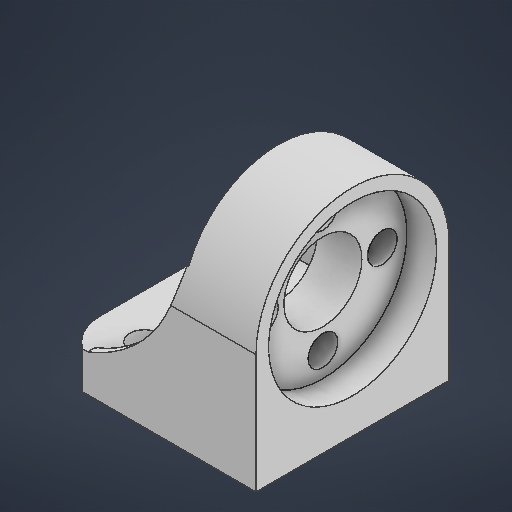
# Autodesk Inventor part: UR_rail_LeadNutHolder_v1
Saved by Autodesk Inventor 2026.2 (Build 302298010, 298A)
## iProperties
Created: 2025-11-14
Part Number: UR_rail_LeadNutHolder_v1
Material: 일반
Document SubType Name: Modeling
Designer: work
Density: 1 g/cm^3
Appearance: 기본값
Author: work
Autodesk Inventor part; units mm, degrees
ref_plane "YZ Plane" through (0, 0, 0) normal (1, 0, 0) x (0, 1, 0)
ref_plane "XZ Plane" through (0, 0, 0) normal (0, 1, 0) x (-1, 0, 0)
ref_plane "XY Plane" through (0, 0, 0) normal (0, 0, 1) x (1, 0, 0)
sketch "스케치1" plane through (0, 0, 0) normal (0, 1, 0) x (-1, 0, 0)
  line L0 (0, 8) -> (0, -8) construction
  line L1 (-6, 8) -> (-6, -8)
  line L2 (6, -8) -> (6, 8)
  arc A0 (6, 8) -> (-6, 8) centre (0, 8) ccw
  arc A1 (-6, -8) -> (6, -8) centre (0, -8) ccw
  circle A2 centre (0, 8) radius 2
  circle A3 centre (0, -8) radius 2
  line L3 (-20, 15) -> (-20, -15)
  line L4 (0, 0) -> (-20, 0) construction
  line L5 (-20, 15) -> (-10, 15)
  arc A4 (1.1881, 13.8812) -> (-10, 15) centre (-10, -41.5) ccw
  line L6 (-20, -15) -> (-10, -15)
  arc A5 (-10, -15) -> (1.1881, -13.8812) centre (-10, 41.5) ccw
  point P0 (1.1881, -13.8812)
  dimension "d0" = 16
  dimension "d1" = 6
  dimension "d2" = 4
  dimension "d3" = 4
  dimension "d4" = 20
  dimension "d5" = 30
  dimension "d6" = 10
  constraints: 16 end point, 9 point on circle, 6 centre point, 6 tangent, 3 symmetric about line, 2 coincident, 2 midpoint, 2 vertical, 1 horizontal, 1 parallel, 1 perpendicular, 1 other
  measures "d0" distance of L0.start L0.end
  measures "d1" radius of A1
  measures "d2" diameter of A2
  measures "d3" diameter of A3
  measures "d4" distance of L4.end L4.start
  measures "d5" distance of L3.start L3.end
  measures "d6" distance of L3.start L5.end
extrude "돌출1" add sketch "스케치1" along normal blind 5
sketch "스케치2" plane through (0, 5, 0) normal (0, 1, 0) x (1, 0, 0)
  line L0 (20, -15) -> (20, 15) projected
  arc A0 (10, 15) -> (-1.1881, 13.8812) centre (10, -41.5) ccw projected
  line L1 (20, -15) -> (10, -15)
  line L2 (10, -15) -> (10, 15)
  line L3 (10, 15) -> (20, 15)
  line L4 (20, 15) -> (20, -15)
  line L5 (-6, 8) -> (-6, -8) projected
  arc A1 (-6, -8) -> (-1.1881, -13.8812) centre (0, -8) ccw projected
  arc A2 (-1.1881, -13.8812) -> (10, -15) centre (10, 41.5) ccw projected
  line L6 (10, -15) -> (20, -15) projected
  line L7 (20, -15) -> (20, 15) projected
  line L8 (20, 15) -> (10, 15) projected
  arc A3 (10, 15) -> (-1.1881, 13.8812) centre (10, -41.5) ccw projected
  arc A4 (-1.1881, 13.8812) -> (-6, 8) centre (0, 8) ccw projected
  circle A5 centre (0, -8) radius 2 projected
  circle A6 centre (0, 8) radius 2 projected
  line L9 (20, 0) -> (-6, 0)
  arc A7 (-0.7921, -11.9208) -> (10, -13) centre (10, 41.5) ccw
  arc A8 (-4, -8) -> (-0.7921, -11.9208) centre (0, -8) ccw
  line L10 (-4, -8) -> (-4, 8)
  arc A9 (-0.7921, 11.9208) -> (-4, 8) centre (0, 8) ccw
  arc A10 (10, 13) -> (-0.7921, 11.9208) centre (10, -41.5) ccw
  line L11 (10, 13) -> (18, 13)
  line L12 (18, 13) -> (18, -13)
  line L13 (18, -13) -> (10, -13)
  line L14 (-7.8326, -10) -> (-13.2379, -10)
  line L15 (-7.8326, 10) -> (-13.2379, 10)
  point P0 (0, 0)
  point P1 (-2.6491, 10)
  point P2 (0.5132, 10)
  point P3 (10, -13)
  point P4 (10, 13)
  point P5 (10, -13)
  dimension "d26" = 2
  dimension "d27" = 10
  constraints: 22 end point, 10 point on circle, 4 centre point, 2 horizontal, 2 midpoint, 2 parallel, 2 symmetric about line, 1 perpendicular, 7 other
  measures "d26" radial gap between concentric circles of A2 A7
  measures "d27" distance between parallel lines of L9 L14
sketch "스케치3" plane through (20, 0, 15) normal (1, 0, 0) x (0, 0, -1)
  line L0 (15, 0) -> (15, 5) construction
  line L1 (23, 5) -> (7, 5) construction
  line L2 (15, 5) -> (15, 16) construction
  circle A0 centre (15, 16) radius 5.25
  circle A1 centre (15, 16) radius 15
  line L3 (0, 16) -> (0, 5)
  line L4 (0, 5) -> (30, 5) projected
  line L5 (30, 16) -> (30, 5)
  line L6 (30, 16) -> (0, 16) construction
  point P0 (0, 10.5)
  dimension "d9" = 11
  dimension "d10" = 10.5
  dimension "d11" = 30
  constraints: 10 end point, 2 centre point, 2 coincident, 2 midpoint, 2 point on circle, 2 vertical, 1 horizontal, 1 point on line
  measures "d9" distance of L0.end L2.end
  measures "d10" diameter of A0
  measures "d11" diameter of A1
extrude "돌출2" add sketch "스케치3" against normal blind 10 contours A1 L4 | L5 L4 A1 | A1 L4 L3 picked at (15.2109, 6.9294)
sketch "스케치4" plane through (20, 0, 15) normal (1, 0, 0) x (0, 0, -1)
  circle A0 centre (15, 16) radius 5.25 projected
  line L0 (0, 0) -> (30, 0) projected
  line L1 (30, 0) -> (30, 16) projected
  arc A1 (30, 16) -> (0, 16) centre (15, 16) ccw projected
  line L2 (0, 0) -> (0, 16) projected
  circle A2 centre (15, 16) radius 11.3
  point P0 (15, 0)
  dimension "d15" = 22.6
  constraints: 1 centre point, 1 coincident
  measures "d15" diameter of A2
extrude "돌출3" cut sketch "스케치4" against normal blind 4 contours A2
sketch "스케치5" plane through (16, 16, 0) normal (1, 0, 0) x (0, 0, -1)
  circle A0 centre (0, 0) radius 11.3 projected
  circle A1 centre (0, 0) radius 5.25 projected
  line L0 (0, 0) -> (0, 8) construction
  circle A2 centre (0, 8) radius 2
  circle A3 centre (-8, 0) radius 2
  circle A4 centre (0, -8) radius 2
  circle A5 centre (8, 0) radius 2
  point P0 (0, -16)
  dimension "d18" = 8
  dimension "d19" = 4
  dimension "d22" = 360
  constraints: 4 centre point, 2 end point, 1 coincident, 1 vertical, 9 other
  measures "d18" distance of L0.start L0.end
  measures "d19" diameter of A2
extrude "돌출4" cut sketch "스케치5" against normal through all contours A2 | A3 | A4 | A5
extrude "돌출5" add sketch "스케치2" along normal up to surface contours A2 A1 L5 L9 L10 A8 A7 L2 | A7 A8 L10 L9 L2 | L2 A10 A9 L10 L9 L5 A4 A0 | L9 L10 A9 A10 L2 | A5 | A6 round surface about axis through (20, 16, 0) along (-1, 0, 0) radius 15 far side no
sketch "스케치6" plane through (20, 0, -15) normal (0, 0, -1) x (-1, 0, 0)
  line L0 (0, 16) -> (0, 16) projected
  line L1 (0, 16) -> (10, 16) projected
  line L2 (0, 16) -> (10, 16) projected
  line L3 (10, 0) -> (21.1881, 0) projected
  line L4 (21.1881, 0) -> (21.1881, 21.6844) projected
  line L5 (10, 0) -> (10, 16) projected
  arc A0 (10, 23.4833) -> (22.6491, 5) centre (29.8288, 23.4833) ccw
  line L6 (10, 23.4833) -> (10, 31) projected
  line L7 (26, 28.6886) -> (26, 28.6886) projected
  line L8 (22.6491, 5) -> (26, 5)
  line L9 (10, 31) -> (31.9721, 34.8576)
  line L10 (31.9721, 34.8576) -> (35.0769, 14.1201)
  line L11 (35.0769, 14.1201) -> (26, 5)
  point P0 (20, 0)
  constraints: 8 end point, 2 point on circle, 1 centre point, 1 horizontal, 1 tangent, 5 other
extrude "돌출6" cut sketch "스케치6" against normal through all
fillet "모깎기2" [suppressed]
fillet "모깎기3" [suppressed]
sketch "스케치9" plane through (-2.6491, 5, 13.3835) normal (0, 1, 0) x (1, 0, 0)
  line L0 (18.6491, 25.3835) -> (-3.3509, 25.3835)
  line L1 (-3.3509, 25.3835) -> (-3.3509, 1.3835)
  line L2 (-3.3509, 1.3835) -> (18.6491, 1.3835)
  line L3 (18.6491, 1.3835) -> (18.6491, 25.3835)
  line L4 (18.6491, 24.6835) -> (18.6491, 2.0835) projected
  line L5 (22.6491, 24.6835) -> (22.6491, 2.0835) projected
  line L6 (-3.3509, 21.3835) -> (-3.3509, 5.3835) projected
  arc A0 (1.461, 27.2647) -> (-3.3509, 21.3835) centre (2.6491, 21.3835) ccw projected
  arc A1 (12.6491, 28.3835) -> (1.461, 27.2647) centre (12.6491, -28.1165) ccw projected
  line L7 (22.6491, 28.3835) -> (12.6491, 28.3835) projected
  line L8 (22.6491, -1.6165) -> (22.6491, 28.3835) projected
  line L9 (12.6491, -1.6165) -> (22.6491, -1.6165) projected
  arc A2 (1.461, -0.4977) -> (12.6491, -1.6165) centre (12.6491, 54.8835) ccw projected
  arc A3 (-3.3509, 5.3835) -> (1.461, -0.4977) centre (2.6491, 5.3835) ccw projected
  circle A4 centre (2.6491, 5.3835) radius 2 projected
  circle A5 centre (2.6491, 21.3835) radius 2 projected
  line L10 (12.6491, 25.3835) -> (12.6491, 1.3835)
  point P0 (2.6491, 13.3835)
  point P1 (18.6491, 13.3835)
  point P2 (-3.3509, 13.3835)
  point P3 (22.6491, 13.3835)
  point P4 (12.6491, 13.3835)
  point P5 (-1.823, 25.3835)
  point P6 (-3.3509, 5.3835)
  point P7 (-1.823, 1.3835)
  dimension "d34" = 3
  dimension "d35" = 10
  constraints: 10 end point, 6 midpoint, 2 parallel, 2 perpendicular, 2 point on line, 1 horizontal
  measures "d34" distance between parallel lines of L7 L0
  measures "d35" distance of point (22.649, 13.384) point (12.649, 13.384)
extrude "돌출7" cut sketch "스케치9" along normal through all contours L10 L2 A3 L1 A0 L0 | A4 | A5
sketch "스케치10" plane through (20, 0, 15) normal (1, 0, 0) x (0, 0, -1)
  circle A0 centre (15, 16) radius 11.3 projected
  line L0 (0, 0) -> (30, 0) projected
  line L1 (30, 0) -> (30, 16) projected
  arc A1 (30, 16) -> (0, 16) centre (15, 16) ccw projected
  line L2 (0, 0) -> (0, 16) projected
  arc A2 (28, 16) -> (2, 16) centre (15, 16) ccw
  line L3 (28, 16) -> (28, 2)
  line L4 (28, 2) -> (2, 2)
  line L5 (2, 2) -> (2, 16)
  line L6 (15, 16) -> (15, 31) construction
  line L7 (2, 2) -> (2, 0)
  line L8 (28, 2) -> (28, 0)
  point P0 (15, 0)
  point P1 (15, 29)
  dimension "d38" = 13
  constraints: 12 end point, 4 point on circle, 2 point on line, 1 centre point, 1 perpendicular, 1 vertical, 3 other
  measures "d38" distance of A0.centre point (15, 29)
extrude "돌출8" cut sketch "스케치10" against normal through all contours L2 A1 L1 L0 L8 L3 A2 L5 L7
